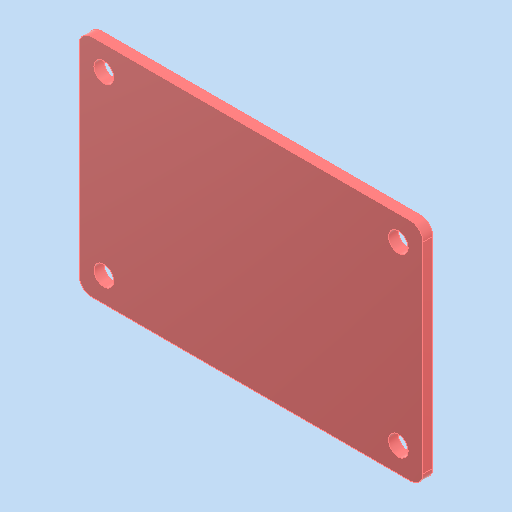
# Autodesk Inventor part: Feetech-controller
Saved by Autodesk Inventor 2025.3 (Build 293356030, 356C)
## iProperties
Created: 2025-08-01
Part Number: Feetech-controller
Material: 一般
Document SubType Name: Modeling
Designer: ibuki_ono
Density: 1 g/cm^3
Appearance: 滑らか - 赤
Author: ibuki_ono
Autodesk Inventor part; units mm, degrees
ref_plane "YZ Plane" through (0, 0, 0) normal (1, 0, 0) x (0, 1, 0)
ref_plane "XZ Plane" through (0, 0, 0) normal (0, 1, 0) x (-1, 0, 0)
ref_plane "XY Plane" through (0, 0, 0) normal (0, 0, 1) x (1, 0, 0)
sketch "スケッチ1" plane through (0, 0, 0) normal (0, 0, 1) x (1, 0, 0)
  line L0 (-27.9, -18.3) -> (27.9, -18.3)
  line L1 (27.9, -18.3) -> (27.9, 18.3)
  line L2 (27.9, 18.3) -> (-27.9, 18.3)
  line L3 (-27.9, 18.3) -> (-27.9, -18.3)
  line L4 (-27.9, -18.3) -> (27.9, 18.3) construction
  line L5 (27.9, -18.3) -> (-27.9, 18.3) construction
  point P0 (0, 0)
  dimension "d0" = 55.8
  dimension "d1" = 36.6
  constraints: 12 end point, 2 midpoint, 2 parallel, 1 horizontal, 1 perpendicular
  measures "d0" distance of L2.end L1.end
  measures "d1" distance of L1.end L0.end
extrude "押し出し1" add sketch "スケッチ1" along normal mid plane 1.6
sketch "スケッチ2" plane through (0, 0, 0.8) normal (0, 0, 1) x (1, 0, 0)
  line L0 (-23.9, -14.3) -> (23.9, -14.3) construction
  line L1 (23.9, -14.3) -> (23.9, 14.3) construction
  line L2 (23.9, 14.3) -> (-23.9, 14.3) construction
  line L3 (-23.9, 14.3) -> (-23.9, -14.3) construction
  line L4 (-23.9, -14.3) -> (23.9, 14.3) construction
  line L5 (23.9, -14.3) -> (-23.9, 14.3) construction
  line L6 (27.9, 18.3) -> (-27.9, 18.3) projected
  line L7 (-27.9, 18.3) -> (-27.9, -18.3) projected
  point P0 (0, 0)
  dimension "d13" = 4
  dimension "d14" = 4
  constraints: 12 end point, 2 midpoint, 2 parallel, 1 horizontal, 1 perpendicular
  measures "d13" distance between parallel lines of L6 L2
  measures "d14" distance between parallel lines of L7 L3
hole "穴1" at (-23.9, 14.3, 0.8) at (-23.9, -14.3, 0.8) at (23.9, 14.3, 0.8) at (23.9, -14.3, 0.8) direction (0, 0, -1) diameter 3.2 end through all
fillet "フィレット1" radius 2 4 edges at (-27.9, 18.3, 0) (-27.9, -18.3, 0) (27.9, -18.3, 0) (27.9, 18.3, 0)
equation "\"d14\" = d13"
